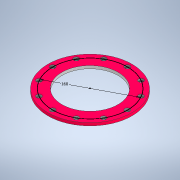
# Autodesk Inventor part: capac_felinar_gaurit
Saved by Autodesk Inventor 2022.6 (Build 266554000, 554)
## iProperties
Created: 2025-06-10
Part Number: capac_felinar_gaurit
Material: Generic
Document SubType Name: Modeling
Designer: Dragos Macovei
Density: 1 g/cm^3
Appearance: Default
Author: Dragos Macovei
Autodesk Inventor part; units mm, degrees
ref_plane "YZ Plane" through (0, 0, 0) normal (1, 0, 0) x (0, 1, 0)
ref_plane "XZ Plane" through (0, 0, 0) normal (0, 1, 0) x (-1, 0, 0)
ref_plane "XY Plane" through (0, 0, 0) normal (0, 0, 1) x (1, 0, 0)
sketch "Sketch1" plane through (0, 0, 0) normal (0, 1, 0) x (-1, 0, 0)
  circle A0 centre (0, 0) radius 90
  dimension "d0" = 180
  constraints: 1 centre point, 1 coincident
  measures "d0" diameter of A0
extrude "Extrusion1" add sketch "Sketch1" along normal blind 6
sketch "Sketch2" plane through (0, 6, 0) normal (0, 1, 0) x (1, 0, 0)
  circle A0 centre (0, 0) radius 80
  dimension "d3" = 160
  constraints: 1 centre point, 1 coincident
  measures "d3" diameter of A0
sketch "Sketch3" plane through (0, 6, 0) normal (0, 1, 0) x (1, 0, 0)
  circle A0 centre (0, 0) radius 90 projected
  line L0 (0, 99.4202) -> (0, -108.8081) construction
  line L1 (-137.3379, 0) -> (196.8442, 0) construction
  circle A1 centre (0, 0) radius 90 projected
  circle A2 centre (0, 0) radius 80 projected
  circle A3 centre (0, 80) radius 5.25
  circle A4 centre (-40, 69.282) radius 5.25
  circle A5 centre (-69.282, 40) radius 5.25
  circle A6 centre (-80, 0) radius 5.25
  circle A7 centre (-69.282, -40) radius 5.25
  circle A8 centre (-40, -69.282) radius 5.25
  circle A9 centre (0, -80) radius 5.25
  circle A10 centre (40, -69.282) radius 5.25
  circle A11 centre (69.282, -40) radius 5.25
  circle A12 centre (80, 0) radius 5.25
  circle A13 centre (69.282, 40) radius 5.25
  circle A14 centre (40, 69.282) radius 5.25
  dimension "d29" = 10.5
  dimension "d32" = 360
  constraints: 12 centre point, 4 end point, 1 horizontal, 1 point on line, 1 vertical, 1 vertical alignment, 26 other
  measures "d29" diameter of A3
extrude "Extrusion2" cut sketch "Sketch3" against normal through all contours A2 A12 | A2 A12 | A13 A2 | A2 A13 | A11 A2 | A2 A11 | A14 A2 | A2 A14 | A10 A2 | A2 A10 | A3 A2 | A2 A3 | A9 A2 | A2 A9 | A4 A2 | A2 A4 | A8 A2 | A2 A8 | A5 A2 | A2 A5 | A7 A2 | A2 A7 | A6 A2 | A2 A6
sketch "Sketch6" plane through (0, 6, 0) normal (0, 1, 0) x (1, 0, 0)
  circle A0 centre (0, 0) radius 60
  dimension "d21" = 120
  constraints: 1 centre point, 1 coincident
  measures "d21" diameter of A0
extrude "Extrusion3" cut sketch "Sketch6" against normal through all
body "Solid1"
